Ikea Lamp Desk Mount (Autodesk Fusion 360 design; units mm, degrees)
Autodesk Fusion 360 part; units mm, degrees
sketch "Sketch1" plane through (0, 0, 0) normal (0, 1, 0) x (1, 0, 0)
  circle A0 centre (0, 0) radius 6.65
  line L0 (-11.65, 0) -> (-11.65, 17.1267)
  line L1 (0.1661, 11.6479) -> (-18, 11.6479)
  line L2 (-11.65, 11.6479) -> (11.65, 11.6479)
  line L3 (11.65, 11.6479) -> (11.65, -11.6479)
  line L4 (11.65, -11.6479) -> (-11.65, -11.6479)
  line L5 (-11.65, -11.6479) -> (-11.65, 11.6479)
  line L6 (-11.65, 11.6479) -> (11.65, -11.6479) construction
  line L7 (11.65, 11.6479) -> (-11.65, -11.6479) construction
  constraint coincident A0.centre origin
  constraint perpendicular L0 L1
  constraint perpendicular L2 L3
  constraint parallel L2 L4
  constraint parallel L3 L5
  constraint horizontal L2
  constraint coincident L1 L2.start
  constraint coincident L0 L2.start
  constraint coincident L6 A0.centre
  constraint coincident L7 A0.centre
extrude "Extrude1" add sketch "Sketch1" along normal blind 42
sketch "Sketch2" plane through (0, 0, -11.6479) normal (0, 0, -1) x (-1, 0, 0)
  line L0 (-11.65, 0) -> (11.65, 0)
  line L1 (11.65, 0) -> (11.65, 42)
  line L2 (11.65, 42) -> (-11.65, 42)
  line L3 (-11.65, 42) -> (-11.65, 0)
  line L4 (11.65, 42) -> (-11.65, 42)
  line L5 (-11.65, 42) -> (-11.65, 38)
  line L6 (-11.65, 38) -> (11.65, 38)
  line L7 (11.65, 38) -> (11.65, 42)
  line L8 (11.65, 0) -> (-11.65, 0)
  line L9 (-11.65, 0) -> (-11.65, 4)
  line L10 (-11.65, 4) -> (11.65, 4)
  line L11 (11.65, 4) -> (11.65, 0)
  dimension "d6" = 4
  dimension "d7" = 4
  constraint horizontal L4
  constraint vertical L5
  constraint horizontal L6
  constraint vertical L7
  constraint coincident L1.end L2.start
  constraint horizontal L8
  constraint vertical L9
  constraint horizontal L10
  constraint vertical L11
  constraint coincident L0.end L1.start
  measures "d6" distance of L1.end L6.end
  measures "d7" distance of L0.end L10.end
extrude "Extrude2" add sketch "Sketch2" along normal blind 40 contours L0 L1 L3 L8 L9 L10 L11 | L1 L2 L3 L4 L5 L6 L7
